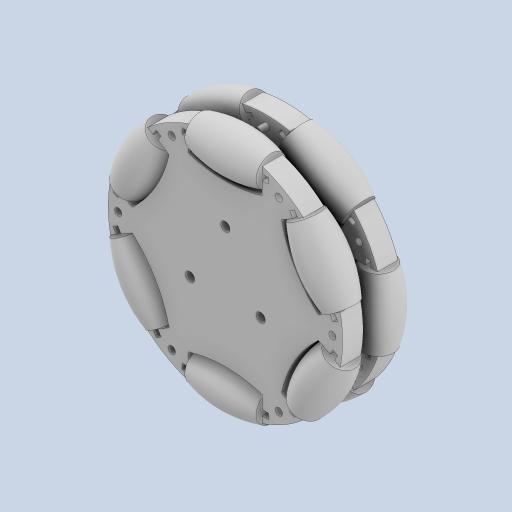
# Autodesk Inventor part: roda
Saved by Autodesk Inventor 2024.3 (Build 283343000, 343)
## iProperties
Created: 2024-12-26
Part Number: roda
Material: Genérico
Document SubType Name: Modeling
Designer: Cliente
Density: 1 g/cm^3
Appearance: Padrão
Author: Cliente
Autodesk Inventor part; units mm, degrees
ref_plane "YZ Plane" through (0, 0, 0) normal (1, 0, 0) x (0, 1, 0)
ref_plane "XZ Plane" through (0, 0, 0) normal (0, 1, 0) x (-1, 0, 0)
sketch "Esboço1" plane through (0, 0, 0) normal (0, 0, 1) x (1, 0, 0)
  circle A0 centre (0, 0) radius 60
  line L0 (-17.5, 50) -> (17.5, 50)
  line L1 (-17.5, 50) -> (-17.5, 57.3912)
  line L2 (17.5, 50) -> (17.5, 57.3912)
  line L3 (-17.5, 51.6) -> (17.5, 51.6)
  point P0 (0, 50)
  dimension "d0" = 120
  dimension "d1" = 35
  dimension "d2" = 50
  dimension "d27" = 1.6
  dimension "d28" = 5.7912
  constraints: 8 end point, 2 point on circle, 2 point on line, 1 centre point, 1 coincident, 1 horizontal, 1 midpoint, 1 parallel, 1 perpendicular, 1 vertical, 1 vertical alignment
  measures "d0" diameter of A0
  measures "d1" distance of L0.start L0.end
  measures "d2" distance of point (0, 0) point (0, 50)
  measures "d27" distance between parallel lines of L0 L3
  measures "d28" distance from line of L3 L1.end
revolve "Revolução1" add sketch "Esboço1" angle 360 about axis through (-17.5, 50, 0) along (1, 0, 0) contours L2 L3 L1 A0
pattern_circular "Padrão circular1" count 6 over 360 about axis through (0, 0, -10) along (0, 0, 1) of "Revolução1"
sketch "Esboço2" plane through (-17.5, 50, 0) normal (-1, 0, 0) x (0, 0, 1)
  circle A0 centre (0, 0) radius 7.3912 projected
  circle A1 centre (0, 0) radius 2.5
  point P0 (0, -50)
  dimension "d7" = 5
  constraints: 1 centre point, 1 coincident
  measures "d7" diameter of A1
extrude "Extrusão1" [suppressed]
pattern_circular "Padrão circular2" [suppressed]
ref_plane "Plano de trabalho1" through (0, 0, -20) normal (0, 0, 1) x (1, 0, 0)
sketch "Esboço3" plane through (0, 0, -20) normal (0, 0, 1) x (1, 0, 0)
  circle A0 centre (0, 0) radius 60
  line L0 (9.8446, 52.0513) -> (40.1554, 34.5513)
  line L1 (9.8446, 52.0513) -> (44.8446, 52.0513) construction
  line L2 (0, 0) -> (25, 43.3013)
  line L3 (0, 0) -> (50, 0) construction
  line L4 (9.8446, 52.0513) -> (13.5402, 58.4522)
  line L5 (40.1554, 34.5513) -> (43.851, 40.9522)
  line L6 (10.6446, 53.4369) -> (40.9554, 35.9369)
  dimension "d16" = 120
  dimension "d23" = 35
  dimension "d24" = 30
  dimension "d25" = 50
  dimension "d26" = 60
  dimension "d29" = 1.6
  constraints: 14 end point, 3 perpendicular, 2 equal length, 2 horizontal, 2 point on circle, 2 point on line, 1 centre point, 1 coincident, 1 midpoint
  measures "d16" diameter of A0
  measures "d23" distance of L0.start L0.end
  measures "d24" angle of L0 L1
  measures "d25" distance of L2.end L2.start
  measures "d26" angle of L3 L2
  measures "d29" distance between parallel lines of L0 L6
revolve "Revolução2" add sketch "Esboço3" angle 360 about axis through (9.8446, 52.0513, -20) along (0.866, -0.5, 0) contours L5 L6 L4 A0
pattern_circular "Padrão circular3" count 6 over 360 about axis through (0, 0, -10) along (0, 0, 1) of "Revolução2"
sketch "Esboço4" plane through (0, 0, -20) normal (0, 0, 1) x (1, 0, 0)
  circle A0 centre (0, 0) radius 57.5
  line L0 (0, 0) -> (-50, 0)
  line L1 (-48.85, -21) -> (-51.15, -21)
  line L2 (-51.15, -21) -> (-51.15, 21)
  line L3 (-51.15, 21) -> (-48.85, 21)
  line L4 (-48.85, 21) -> (-48.85, -21)
  line L5 (-48.85, -21) -> (-51.15, 21) construction
  line L6 (-51.15, -21) -> (-48.85, 21) construction
  line L7 (-48.7, -21.15) -> (-51.3, -21.15)
  line L8 (-51.3, -21.15) -> (-51.3, 21.15)
  line L9 (-51.3, 21.15) -> (-48.7, 21.15)
  line L10 (-48.7, 21.15) -> (-48.7, -21.15)
  line L11 (-6.2385, -52.8053) -> (-7.3885, -54.7972)
  line L12 (-7.3885, -54.7972) -> (-43.7615, -33.7972)
  line L13 (-43.7615, -33.7972) -> (-42.6115, -31.8053)
  line L14 (-42.6115, -31.8053) -> (-6.2385, -52.8053)
  line L15 (-6.2385, -52.8053) -> (-43.7615, -33.7972) construction
  line L16 (-7.3885, -54.7972) -> (-42.6115, -31.8053) construction
  line L17 (-6.0336, -52.7504) -> (-7.3336, -55.0021)
  line L18 (-7.3336, -55.0021) -> (-43.9664, -33.8521)
  line L19 (-43.9664, -33.8521) -> (-42.6664, -31.6004)
  line L20 (-42.6664, -31.6004) -> (-6.0336, -52.7504)
  line L21 (42.6115, -31.8053) -> (43.7615, -33.7972)
  line L22 (43.7615, -33.7972) -> (7.3885, -54.7972)
  line L23 (7.3885, -54.7972) -> (6.2385, -52.8053)
  line L24 (6.2385, -52.8053) -> (42.6115, -31.8053)
  line L25 (42.6115, -31.8053) -> (7.3885, -54.7972) construction
  line L26 (43.7615, -33.7972) -> (6.2385, -52.8053) construction
  line L27 (42.6664, -31.6004) -> (43.9664, -33.8521)
  line L28 (43.9664, -33.8521) -> (7.3336, -55.0021)
  line L29 (7.3336, -55.0021) -> (6.0336, -52.7504)
  line L30 (6.0336, -52.7504) -> (42.6664, -31.6004)
  line L31 (48.85, 21) -> (51.15, 21)
  line L32 (51.15, 21) -> (51.15, -21)
  line L33 (51.15, -21) -> (48.85, -21)
  line L34 (48.85, -21) -> (48.85, 21)
  line L35 (48.85, 21) -> (51.15, -21) construction
  line L36 (51.15, 21) -> (48.85, -21) construction
  line L37 (48.7, 21.15) -> (51.3, 21.15)
  line L38 (51.3, 21.15) -> (51.3, -21.15)
  line L39 (51.3, -21.15) -> (48.7, -21.15)
  line L40 (48.7, -21.15) -> (48.7, 21.15)
  line L41 (6.2385, 52.8053) -> (7.3885, 54.7972)
  line L42 (7.3885, 54.7972) -> (43.7615, 33.7972)
  line L43 (43.7615, 33.7972) -> (42.6115, 31.8053)
  line L44 (42.6115, 31.8053) -> (6.2385, 52.8053)
  line L45 (6.2385, 52.8053) -> (43.7615, 33.7972) construction
  line L46 (7.3885, 54.7972) -> (42.6115, 31.8053) construction
  line L47 (6.0336, 52.7504) -> (7.3336, 55.0021)
  line L48 (7.3336, 55.0021) -> (43.9664, 33.8521)
  line L49 (43.9664, 33.8521) -> (42.6664, 31.6004)
  line L50 (42.6664, 31.6004) -> (6.0336, 52.7504)
  line L51 (-42.6115, 31.8053) -> (-43.7615, 33.7972)
  line L52 (-43.7615, 33.7972) -> (-7.3885, 54.7972)
  line L53 (-7.3885, 54.7972) -> (-6.2385, 52.8053)
  line L54 (-6.2385, 52.8053) -> (-42.6115, 31.8053)
  line L55 (-42.6115, 31.8053) -> (-7.3885, 54.7972) construction
  line L56 (-43.7615, 33.7972) -> (-6.2385, 52.8053) construction
  line L57 (-42.6664, 31.6004) -> (-43.9664, 33.8521)
  line L58 (-43.9664, 33.8521) -> (-7.3336, 55.0021)
  line L59 (-7.3336, 55.0021) -> (-6.0336, 52.7504)
  line L60 (-6.0336, 52.7504) -> (-42.6664, 31.6004)
  line L61 (-42.6088, 17.5) -> (-57.3912, 17.5) projected
  line L62 (-42.6088, -17.5) -> (-57.3912, -17.5) projected
  line L63 (-42.6088, 17.5) -> (-57.3912, 17.5) projected
  arc A1 (-42.6088, -17.5) -> (-42.6088, 17.5) centre (-100, 0) ccw projected
  line L64 (-42.2397, -18) -> (-54.61, -18)
  arc A2 (-42.2397, -18) -> (-42.2397, 18) centre (-100, 0) ccw
  line L65 (-42.2397, 18) -> (-54.61, 18)
  line L66 (-36.7083, -27.5807) -> (-42.8934, -38.2936)
  arc A3 (-5.5314, -45.5807) -> (-36.7083, -27.5807) centre (-50, -86.6025) ccw
  line L67 (-5.5314, -45.5807) -> (-11.7165, -56.2936)
  line L68 (5.5314, -45.5807) -> (11.7165, -56.2936)
  arc A4 (36.7083, -27.5807) -> (5.5314, -45.5807) centre (50, -86.6025) ccw
  line L69 (36.7083, -27.5807) -> (42.8934, -38.2936)
  line L70 (42.2397, -18) -> (54.61, -18)
  arc A5 (42.2397, 18) -> (42.2397, -18) centre (100, 0) ccw
  line L71 (42.2397, 18) -> (54.61, 18)
  line L72 (36.7083, 27.5807) -> (42.8934, 38.2936)
  arc A6 (5.5314, 45.5807) -> (36.7083, 27.5807) centre (50, 86.6025) ccw
  line L73 (5.5314, 45.5807) -> (11.7165, 56.2936)
  line L74 (-5.5314, 45.5807) -> (-11.7165, 56.2936)
  arc A7 (-36.7083, 27.5807) -> (-5.5314, 45.5807) centre (-50, 86.6025) ccw
  line L75 (-36.7083, 27.5807) -> (-42.8934, 38.2936)
  line L76 (0, 0) -> (0, 52.5)
  circle A8 centre (0, 52.5) radius 1.75
  circle A9 centre (-45.4663, 26.25) radius 1.75
  circle A10 centre (-45.4663, -26.25) radius 1.75
  circle A11 centre (0, -52.5) radius 1.75
  circle A12 centre (45.4663, -26.25) radius 1.75
  circle A13 centre (45.4663, 26.25) radius 1.75
  point P0 (-25, -43.3013)
  point P1 (25, -43.3013)
  point P2 (50, 0)
  point P3 (25, 43.3013)
  point P4 (-25, 43.3013)
  point P5 (-48.7, -18)
  point P6 (-51.3, -18)
  point P7 (-41.2385, -35.4271)
  point P8 (-39.9385, -33.1754)
  point P9 (-8.7615, -51.1754)
  point P10 (-10.0615, -53.4271)
  point P11 (10.0615, -53.4271)
  point P12 (8.7615, -51.1754)
  point P13 (39.9385, -33.1754)
  point P14 (41.2385, -35.4271)
  point P15 (51.3, -18)
  point P16 (48.7, -18)
  point P17 (48.7, 18)
  point P18 (51.3, 18)
  point P19 (41.2385, 35.4271)
  point P20 (39.9385, 33.1754)
  point P21 (8.7615, 51.1754)
  point P22 (10.0615, 53.4271)
  point P23 (-10.0615, 53.4271)
  point P24 (-8.7615, 51.1754)
  point P25 (-39.9385, 33.1754)
  point P26 (-41.2385, 35.4271)
  point P27 (-51.3, 18)
  point P28 (-48.7, 18)
  dimension "d30" = 115
  dimension "d31" = 50
  dimension "d32" = 2.3
  dimension "d33" = 42
  dimension "d34" = 0.15
  dimension "d37" = 360
  dimension "d39" = 0.5
  dimension "d40" = 0.5
  dimension "d41" = 0.5
  dimension "d44" = 360
  dimension "d46" = 52.5
  dimension "d47" = 3.5
  dimension "d50" = 360
  constraints: 148 end point, 14 point on circle, 13 centre point, 6 parallel, 2 coincident, 2 horizontal, 2 midpoint, 2 perpendicular, 1 vertical, 180 other
  measures "d30" diameter of A0
  measures "d31" distance of L0.start L0.end
  measures "d32" distance of L2.end L3.end
  measures "d33" distance of L1.end L2.end
  measures "d34" distance between parallel lines of L4 L10
  measures "d39" distance between parallel lines of L62 L64
  measures "d40" radial gap between concentric circles of A1 A2
  measures "d41" distance between parallel lines of L61 L65
  measures "d46" distance of L0.start L76.end
  measures "d47" diameter of A8
extrude "Extrusão2" add sketch "Esboço4" along normal mid plane 10 contours L71 L38 L37 L40 A5 L70 L39 A0 L69 L28 L27 L30 A4 L68 L29 L67 L18 L17 L20 A3 L66 L19 L64 L8 L7 L10 A2 L65 L9 L75 L58 L57 L60 A7 L74 L59 L73 L48 L47 L50 A6 L72 L49
sketch "Esboço5" plane through (0, 0, 0) normal (0, 0, 1) x (1, 0, 0)
  circle A0 centre (0, 0) radius 57.5
  line L0 (-17.5, 42.6088) -> (-17.5, 57.3912) projected
  arc A1 (-17.5, 42.6088) -> (17.5, 42.6088) centre (0, 100) ccw projected
  line L1 (17.5, 42.6088) -> (17.5, 57.3912) projected
  line L2 (0, 0) -> (0, 50)
  line L3 (-21, 51.2) -> (21, 51.2)
  line L4 (21, 51.2) -> (21, 48.8)
  line L5 (21, 48.8) -> (-21, 48.8)
  line L6 (-21, 48.8) -> (-21, 51.2)
  line L7 (-21, 51.2) -> (21, 48.8) construction
  line L8 (21, 51.2) -> (-21, 48.8) construction
  line L9 (21.15, 51.35) -> (-21.15, 51.35)
  line L10 (-21.15, 51.35) -> (-21.15, 48.65)
  line L11 (-21.15, 48.65) -> (21.15, 48.65)
  line L12 (21.15, 48.65) -> (21.15, 51.35)
  line L13 (0, 0) -> (52.5, 0)
  circle A2 centre (52.5, 0) radius 1.75
  line L14 (-18, 42.2397) -> (-18, 57.3912)
  arc A3 (-18, 42.2397) -> (18, 42.2397) centre (0, 100) ccw
  line L15 (18, 42.2397) -> (18, 57.3912)
  line L16 (-55.0454, 7.3586) -> (-52.7071, 6.0086)
  line L17 (-52.762, 6.2135) -> (-54.8405, 7.4135)
  line L18 (-54.8405, 7.4135) -> (-33.8405, 43.7865)
  line L19 (-33.8954, 43.9914) -> (-55.0454, 7.3586)
  line L20 (-52.7071, 6.0086) -> (-31.5571, 42.6414)
  line L21 (-31.762, 42.5865) -> (-52.762, 6.2135)
  line L22 (-31.5571, 42.6414) -> (-33.8954, 43.9914)
  line L23 (-33.8405, 43.7865) -> (-31.762, 42.5865)
  arc A4 (-45.5807, 5.5314) -> (-27.5807, 36.7083) centre (-86.6025, 50) ccw
  line L24 (-45.5807, 5.5314) -> (-58.7022, 13.1071)
  line L25 (-27.5807, 36.7083) -> (-40.7022, 44.2841)
  circle A5 centre (26.25, 45.4663) radius 1.75
  line L26 (-33.8954, -43.9914) -> (-31.5571, -42.6414)
  line L27 (-31.762, -42.5865) -> (-33.8405, -43.7865)
  line L28 (-33.8405, -43.7865) -> (-54.8405, -7.4135)
  line L29 (-55.0454, -7.3586) -> (-33.8954, -43.9914)
  line L30 (-31.5571, -42.6414) -> (-52.7071, -6.0086)
  line L31 (-52.762, -6.2135) -> (-31.762, -42.5865)
  line L32 (-52.7071, -6.0086) -> (-55.0454, -7.3586)
  line L33 (-54.8405, -7.4135) -> (-52.762, -6.2135)
  arc A6 (-27.5807, -36.7083) -> (-45.5807, -5.5314) centre (-86.6025, -50) ccw
  line L34 (-27.5807, -36.7083) -> (-40.7022, -44.2841)
  line L35 (-45.5807, -5.5314) -> (-58.7022, -13.1071)
  circle A7 centre (-26.25, 45.4663) radius 1.75
  line L36 (21.15, -51.35) -> (21.15, -48.65)
  line L37 (21, -48.8) -> (21, -51.2)
  line L38 (21, -51.2) -> (-21, -51.2)
  line L39 (-21.15, -51.35) -> (21.15, -51.35)
  line L40 (21.15, -48.65) -> (-21.15, -48.65)
  line L41 (-21, -48.8) -> (21, -48.8)
  line L42 (-21.15, -48.65) -> (-21.15, -51.35)
  line L43 (-21, -51.2) -> (-21, -48.8)
  arc A8 (18, -42.2397) -> (-18, -42.2397) centre (0, -100) ccw
  line L44 (18, -42.2397) -> (18, -57.3912)
  line L45 (-18, -42.2397) -> (-18, -57.3912)
  circle A9 centre (-52.5, 0) radius 1.75
  line L46 (55.0454, -7.3586) -> (52.7071, -6.0086)
  line L47 (52.762, -6.2135) -> (54.8405, -7.4135)
  line L48 (54.8405, -7.4135) -> (33.8405, -43.7865)
  line L49 (33.8954, -43.9914) -> (55.0454, -7.3586)
  line L50 (52.7071, -6.0086) -> (31.5571, -42.6414)
  line L51 (31.762, -42.5865) -> (52.762, -6.2135)
  line L52 (31.5571, -42.6414) -> (33.8954, -43.9914)
  line L53 (33.8405, -43.7865) -> (31.762, -42.5865)
  arc A10 (45.5807, -5.5314) -> (27.5807, -36.7083) centre (86.6025, -50) ccw
  line L54 (45.5807, -5.5314) -> (58.7022, -13.1071)
  line L55 (27.5807, -36.7083) -> (40.7022, -44.2841)
  circle A11 centre (-26.25, -45.4663) radius 1.75
  line L56 (33.8954, 43.9914) -> (31.5571, 42.6414)
  line L57 (31.762, 42.5865) -> (33.8405, 43.7865)
  line L58 (33.8405, 43.7865) -> (54.8405, 7.4135)
  line L59 (55.0454, 7.3586) -> (33.8954, 43.9914)
  line L60 (31.5571, 42.6414) -> (52.7071, 6.0086)
  line L61 (52.762, 6.2135) -> (31.762, 42.5865)
  line L62 (52.7071, 6.0086) -> (55.0454, 7.3586)
  line L63 (54.8405, 7.4135) -> (52.762, 6.2135)
  arc A12 (27.5807, 36.7083) -> (45.5807, 5.5314) centre (86.6025, 50) ccw
  line L64 (27.5807, 36.7083) -> (40.7022, 44.2841)
  line L65 (45.5807, 5.5314) -> (58.7022, 13.1071)
  circle A13 centre (26.25, -45.4663) radius 1.75
  point P0 (-18, 48.65)
  point P1 (-18, 51.35)
  point P2 (-18, 54.61)
  point P3 (-38.2936, 42.8934)
  point P4 (-35.4704, 41.2635)
  point P5 (-33.1321, 39.9135)
  point P6 (-51.1321, 8.7365)
  point P7 (-53.4704, 10.0865)
  point P8 (-56.2936, 11.7165)
  point P9 (-56.2936, -11.7165)
  point P10 (-53.4704, -10.0865)
  point P11 (-51.1321, -8.7365)
  point P12 (-33.1321, -39.9135)
  point P13 (-35.4704, -41.2635)
  point P14 (-38.2936, -42.8934)
  point P15 (-18, -54.61)
  point P16 (-18, -51.35)
  point P17 (-18, -48.65)
  point P18 (18, -48.65)
  point P19 (18, -51.35)
  point P20 (18, -54.61)
  point P21 (38.2936, -42.8934)
  point P22 (35.4704, -41.2635)
  point P23 (33.1321, -39.9135)
  point P24 (51.1321, -8.7365)
  point P25 (53.4704, -10.0865)
  point P26 (56.2936, -11.7165)
  point P27 (56.2936, 11.7165)
  point P28 (53.4704, 10.0865)
  point P29 (51.1321, 8.7365)
  point P30 (33.1321, 39.9135)
  point P31 (35.4704, 41.2635)
  point P32 (38.2936, 42.8934)
  point P33 (18, 54.61)
  point P34 (18, 51.35)
  point P35 (18, 48.65)
  dimension "d54" = 115
  dimension "d55" = 50
  dimension "d56" = 42
  dimension "d57" = 2.4
  dimension "d58" = 0.15
  dimension "d62" = 52.5
  dimension "d63" = 3.5
  dimension "d64" = 0.5
  dimension "d65" = 0.5
  dimension "d66" = 0.5
  dimension "d69" = 360
  constraints: 128 end point, 13 centre point, 12 point on circle, 5 parallel, 2 coincident, 2 horizontal, 2 midpoint, 2 perpendicular, 1 vertical, 160 other
  measures "d54" diameter of A0
  measures "d55" distance of L2.start L2.end
  measures "d56" distance of L4.end L5.end
  measures "d57" distance of L3.end L4.end
  measures "d58" distance between parallel lines of L3 L9
  measures "d62" distance of L2.start L13.end
  measures "d63" diameter of A2
  measures "d64" distance between parallel lines of L0 L14
  measures "d65" radial gap between concentric circles of A1 A3
  measures "d66" distance between parallel lines of L15 L1
extrude "Extrusão3" add sketch "Esboço5" along normal mid plane 10 contours A0 L54 L49 L46 L50 A10 L55 L52 L44 L39 L36 L40 A8 L45 L42 L34 L29 L26 L30 A6 L35 L32 L24 L19 L16 L20 A4 L25 L22 L14 L9 L10 L11 A3 L15 L12 L64 L59 L56 L60 A12 L65 L62
sketch "Esboço6" plane through (0, 0, -5) normal (0, 0, -1) x (-1, 0, 0)
  circle A0 centre (0, 0) radius 35
  dimension "d73" = 70
  constraints: 1 centre point, 1 coincident
  measures "d73" diameter of A0
extrude "Extrusão4" add sketch "Esboço6" along normal blind 10
sketch "Esboço7" plane through (0, 0, 5) normal (0, 0, 1) x (1, 0, 0)
  circle A0 centre (-26.25, 45.4663) radius 1.75 projected
  circle A1 centre (0, 52.5) radius 1.75 projected
  line L0 (-26.25, 45.4663) -> (0, 52.5)
  line L1 (0, 0) -> (-13.125, 48.9832)
  line L2 (0, 0) -> (-5.1764, 19.3185)
  circle A2 centre (-5.1764, 19.3185) radius 2.25
  circle A3 centre (-14.1421, -14.1421) radius 2.25
  circle A4 centre (19.3185, -5.1764) radius 2.25
  line L3 (0, 0) -> (0, 20)
  circle A5 centre (0, 20) radius 2.25
  circle A6 centre (-17.3205, -10) radius 2.25
  circle A7 centre (17.3205, -10) radius 2.25
  dimension "d76" = 20
  dimension "d77" = 4.5
  dimension "d80" = 360
  dimension "d84" = 20
  dimension "d85" = 4.5
  dimension "d88" = 360
  constraints: 8 end point, 6 centre point, 2 coincident, 1 midpoint, 1 point on line, 1 vertical, 14 other
  measures "d76" distance of L1.start L2.end
  measures "d77" diameter of A2
  measures "d84" distance of L1.start L3.end
  measures "d85" diameter of A5
extrude "Extrusão5" [suppressed]
extrude "Extrusão6" cut sketch "Esboço7" against normal through all contours A5 | A6 | A7
sketch "Esboço8" plane through (0, 0, -25) normal (0, 0, -1) x (-1, 0, 0)
  circle A0 centre (0, 52.5) radius 1.75 projected
  circle A1 centre (0, 52.5) radius 1.5
  point P0 (0, 0)
  dimension "d92" = 3
  constraints: 1 centre point, 1 coincident
  measures "d92" diameter of A1
extrude "Extrusão7" add sketch "Esboço8" against normal blind 14.2 contours A1
